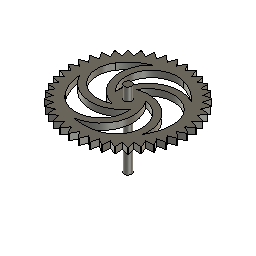
in gear (Autodesk Fusion 360 design; units mm, degrees)
part number: 2026-03-27-23-33-12-431
Autodesk Fusion 360 part; units mm, degrees
sketch "Sketch1" plane through (0, 0, 0) normal (0, 0, 1) x (1, 0, 0)
  circle A0 centre (0, 0) radius 3
  dimension "d1" = 6
  constraint coincident A0.centre origin
  measures "d1" diameter of A0
extrude "Extrude1" add sketch "Sketch1" along normal blind 49.5
sketch "Sketch2" plane through (0, 0, 49.5) normal (0, 0, 1) x (-1, 0, 0)
  circle A0 centre (0, 0) radius 3
  circle A1 centre (0, 0) radius 41
  dimension "d4" = 82
  constraint concentric A0 A1
  measures "d4" diameter of A1
extrude "Extrude2" add sketch "Sketch2" against normal blind 5
sketch "Sketch3" plane through (0, 0, 49.5) normal (0, 0, 1) x (-1, 0, 0)
  circle A0 centre (0, 0) radius 41
  line L0 (-3.4641, -40.8534) -> (0, -46.8534)
  line L1 (0, -46.8534) -> (3.4641, -40.8534)
  line L2 (3.4641, -40.8534) -> (-3.4641, -40.8534)
  point P0 (0, -42.8534)
  dimension "d7" = 2
  constraint horizontal L2
  constraint coincident A0 L1.end
  constraint coincident A0 L0.start
  measures "d7" distance of P0 L2
extrude "Extrude3" add sketch "Sketch3" against normal up to surface (5 mm away) contours A0 L0 L1
fillet "Fillet1" radius 0.5 1 edges at (0, 46.8534, 47)
pattern_circular "C-Pattern1" count 40 over 360 about axis through (0, 0, 1.75) along (0, 0, 1) of "Extrude3", "Fillet1"
sketch "Sketch4" plane through (0, 0, 49.5) normal (0, 0, 1) x (-1, 0, 0)
  arc A0 (-7.6398, -45.468) -> (-6.7845, -45.6035) centre (-7.1731, -45.2889) ccw
  line L0 (-6.7845, -45.6035) -> (-3.2451, -41.2327)
  line L1 (-3.2451, -41.2327) -> (-0.433, -46.1034)
  arc A1 (-0.433, -46.1034) -> (0.433, -46.1034) centre (0, -45.8534) ccw
  line L2 (0.433, -46.1034) -> (3.2451, -41.2327)
  line L3 (3.2451, -41.2327) -> (6.7845, -45.6035)
  arc A2 (6.7845, -45.6035) -> (7.6398, -45.468) centre (7.1731, -45.2889) ccw
  line L4 (7.6398, -45.468) -> (9.6554, -40.2175)
  line L5 (9.6554, -40.2175) -> (13.8349, -43.9807)
  arc A3 (13.8349, -43.9807) -> (14.6586, -43.7131) centre (14.1695, -43.6092) ccw
  line L6 (14.6586, -43.7131) -> (15.8279, -38.2119)
  line L7 (15.8279, -38.2119) -> (20.5447, -41.275)
  arc A4 (20.5447, -41.275) -> (21.3163, -40.8818) centre (20.817, -40.8557) ccw
  line L8 (21.3163, -40.8818) -> (21.6107, -35.2654)
  line L9 (21.6107, -35.2654) -> (26.7486, -37.5529)
  arc A5 (26.7486, -37.5529) -> (27.4492, -37.0439) centre (26.952, -37.0962) ccw
  line L10 (27.4492, -37.0439) -> (26.8613, -31.4506)
  line L11 (26.8613, -31.4506) -> (32.2938, -32.9062)
  arc A6 (32.2938, -32.9062) -> (32.9062, -32.2938) centre (32.4232, -32.4232) ccw
  line L12 (32.9062, -32.2938) -> (31.4506, -26.8613)
  line L13 (31.4506, -26.8613) -> (37.0439, -27.4492)
  arc A7 (37.0439, -27.4492) -> (37.5529, -26.7486) centre (37.0962, -26.952) ccw
  line L14 (37.5529, -26.7486) -> (35.2654, -21.6107)
  line L15 (35.2654, -21.6107) -> (40.8818, -21.3163)
  arc A8 (40.8818, -21.3163) -> (41.275, -20.5447) centre (40.8557, -20.817) ccw
  line L16 (41.275, -20.5447) -> (38.2119, -15.8279)
  line L17 (38.2119, -15.8279) -> (43.7131, -14.6586)
  arc A9 (43.7131, -14.6586) -> (43.9807, -13.8349) centre (43.6092, -14.1695) ccw
  line L18 (43.9807, -13.8349) -> (40.2175, -9.6554)
  line L19 (40.2175, -9.6554) -> (45.468, -7.6398)
  arc A10 (45.468, -7.6398) -> (45.6035, -6.7845) centre (45.2889, -7.1731) ccw
  line L20 (45.6035, -6.7845) -> (41.2327, -3.2451)
  line L21 (41.2327, -3.2451) -> (46.1034, -0.433)
  arc A11 (46.1034, -0.433) -> (46.1034, 0.433) centre (45.8534, 0) ccw
  line L22 (46.1034, 0.433) -> (41.2327, 3.2451)
  line L23 (41.2327, 3.2451) -> (45.6035, 6.7845)
  arc A12 (45.6035, 6.7845) -> (45.468, 7.6398) centre (45.2889, 7.1731) ccw
  line L24 (45.468, 7.6398) -> (40.2175, 9.6554)
  line L25 (40.2175, 9.6554) -> (43.9807, 13.8349)
  arc A13 (43.9807, 13.8349) -> (43.7131, 14.6586) centre (43.6092, 14.1695) ccw
  line L26 (43.7131, 14.6586) -> (38.2119, 15.8279)
  line L27 (38.2119, 15.8279) -> (41.275, 20.5447)
  arc A14 (41.275, 20.5447) -> (40.8818, 21.3163) centre (40.8557, 20.817) ccw
  line L28 (40.8818, 21.3163) -> (35.2654, 21.6107)
  line L29 (35.2654, 21.6107) -> (37.5529, 26.7486)
  arc A15 (37.5529, 26.7486) -> (37.0439, 27.4492) centre (37.0962, 26.952) ccw
  line L30 (37.0439, 27.4492) -> (31.4506, 26.8613)
  line L31 (31.4506, 26.8613) -> (32.9062, 32.2938)
  arc A16 (32.9062, 32.2938) -> (32.2938, 32.9062) centre (32.4232, 32.4232) ccw
  line L32 (32.2938, 32.9062) -> (26.8613, 31.4506)
  line L33 (26.8613, 31.4506) -> (27.4492, 37.0439)
  arc A17 (27.4492, 37.0439) -> (26.7486, 37.5529) centre (26.952, 37.0962) ccw
  line L34 (26.7486, 37.5529) -> (21.6107, 35.2654)
  line L35 (21.6107, 35.2654) -> (21.3163, 40.8818)
  arc A18 (21.3163, 40.8818) -> (20.5447, 41.275) centre (20.817, 40.8557) ccw
  line L36 (20.5447, 41.275) -> (15.8279, 38.2119)
  line L37 (15.8279, 38.2119) -> (14.6586, 43.7131)
  arc A19 (14.6586, 43.7131) -> (13.8349, 43.9807) centre (14.1695, 43.6092) ccw
  line L38 (13.8349, 43.9807) -> (9.6554, 40.2175)
  line L39 (9.6554, 40.2175) -> (7.6398, 45.468)
  arc A20 (7.6398, 45.468) -> (6.7845, 45.6035) centre (7.1731, 45.2889) ccw
  line L40 (6.7845, 45.6035) -> (3.2451, 41.2327)
  line L41 (3.2451, 41.2327) -> (0.433, 46.1034)
  arc A21 (0.433, 46.1034) -> (-0.433, 46.1034) centre (0, 45.8534) ccw
  line L42 (-0.433, 46.1034) -> (-3.2451, 41.2327)
  line L43 (-3.2451, 41.2327) -> (-6.7845, 45.6035)
  arc A22 (-6.7845, 45.6035) -> (-7.6398, 45.468) centre (-7.1731, 45.2889) ccw
  line L44 (-7.6398, 45.468) -> (-9.6554, 40.2175)
  line L45 (-9.6554, 40.2175) -> (-13.8349, 43.9807)
  arc A23 (-13.8349, 43.9807) -> (-14.6586, 43.7131) centre (-14.1695, 43.6092) ccw
  line L46 (-14.6586, 43.7131) -> (-15.8279, 38.2119)
  line L47 (-15.8279, 38.2119) -> (-20.5447, 41.275)
  arc A24 (-20.5447, 41.275) -> (-21.3163, 40.8818) centre (-20.817, 40.8557) ccw
  line L48 (-21.3163, 40.8818) -> (-21.6107, 35.2654)
  line L49 (-21.6107, 35.2654) -> (-26.7486, 37.5529)
  arc A25 (-26.7486, 37.5529) -> (-27.4492, 37.0439) centre (-26.952, 37.0962) ccw
  line L50 (-27.4492, 37.0439) -> (-26.8613, 31.4506)
  line L51 (-26.8613, 31.4506) -> (-32.2938, 32.9062)
  arc A26 (-32.2938, 32.9062) -> (-32.9062, 32.2938) centre (-32.4232, 32.4232) ccw
  line L52 (-32.9062, 32.2938) -> (-31.4506, 26.8613)
  line L53 (-31.4506, 26.8613) -> (-37.0439, 27.4492)
  arc A27 (-37.0439, 27.4492) -> (-37.5529, 26.7486) centre (-37.0962, 26.952) ccw
  line L54 (-37.5529, 26.7486) -> (-35.2654, 21.6107)
  line L55 (-35.2654, 21.6107) -> (-40.8818, 21.3163)
  arc A28 (-40.8818, 21.3163) -> (-41.275, 20.5447) centre (-40.8557, 20.817) ccw
  line L56 (-41.275, 20.5447) -> (-38.2119, 15.8279)
  line L57 (-38.2119, 15.8279) -> (-43.7131, 14.6586)
  arc A29 (-43.7131, 14.6586) -> (-43.9807, 13.8349) centre (-43.6092, 14.1695) ccw
  line L58 (-43.9807, 13.8349) -> (-40.2175, 9.6554)
  line L59 (-40.2175, 9.6554) -> (-45.468, 7.6398)
  arc A30 (-45.468, 7.6398) -> (-45.6035, 6.7845) centre (-45.2889, 7.1731) ccw
  line L60 (-45.6035, 6.7845) -> (-41.2327, 3.2451)
  line L61 (-41.2327, 3.2451) -> (-46.1034, 0.433)
  arc A31 (-46.1034, 0.433) -> (-46.1034, -0.433) centre (-45.8534, 0) ccw
  line L62 (-46.1034, -0.433) -> (-41.2327, -3.2451)
  line L63 (-41.2327, -3.2451) -> (-45.6035, -6.7845)
  arc A32 (-45.6035, -6.7845) -> (-45.468, -7.6398) centre (-45.2889, -7.1731) ccw
  line L64 (-45.468, -7.6398) -> (-40.2175, -9.6554)
  line L65 (-40.2175, -9.6554) -> (-43.9807, -13.8349)
  arc A33 (-43.9807, -13.8349) -> (-43.7131, -14.6586) centre (-43.6092, -14.1695) ccw
  line L66 (-43.7131, -14.6586) -> (-38.2119, -15.8279)
  line L67 (-38.2119, -15.8279) -> (-41.275, -20.5447)
  arc A34 (-41.275, -20.5447) -> (-40.8818, -21.3163) centre (-40.8557, -20.817) ccw
  line L68 (-40.8818, -21.3163) -> (-35.2654, -21.6107)
  line L69 (-35.2654, -21.6107) -> (-37.5529, -26.7486)
  arc A35 (-37.5529, -26.7486) -> (-37.0439, -27.4492) centre (-37.0962, -26.952) ccw
  line L70 (-37.0439, -27.4492) -> (-31.4506, -26.8613)
  line L71 (-31.4506, -26.8613) -> (-32.9062, -32.2938)
  arc A36 (-32.9062, -32.2938) -> (-32.2938, -32.9062) centre (-32.4232, -32.4232) ccw
  line L72 (-32.2938, -32.9062) -> (-26.8613, -31.4506)
  line L73 (-26.8613, -31.4506) -> (-27.4492, -37.0439)
  arc A37 (-27.4492, -37.0439) -> (-26.7486, -37.5529) centre (-26.952, -37.0962) ccw
  line L74 (-26.7486, -37.5529) -> (-21.6107, -35.2654)
  line L75 (-21.6107, -35.2654) -> (-21.3163, -40.8818)
  arc A38 (-21.3163, -40.8818) -> (-20.5447, -41.275) centre (-20.817, -40.8557) ccw
  line L76 (-20.5447, -41.275) -> (-15.8279, -38.2119)
  line L77 (-15.8279, -38.2119) -> (-14.6586, -43.7131)
  arc A39 (-14.6586, -43.7131) -> (-13.8349, -43.9807) centre (-14.1695, -43.6092) ccw
  line L78 (-13.8349, -43.9807) -> (-9.6554, -40.2175)
  line L79 (-9.6554, -40.2175) -> (-7.6398, -45.468)
  circle A40 centre (0, 0) radius 35
  circle A41 centre (0, 0) radius 5
  arc A42 (-34.9762, -1.2899) -> (4.9966, 0.1843) centre (-14.9898, -0.5528) ccw
  arc A43 (-26.6834, -22.6495) -> (10.0084, -0.2575) centre (-14.9898, -0.5528) ccw
  arc A44 (-9.5814, -33.663) -> (1.3688, 4.809) centre (-4.1063, -14.427) ccw
  arc A45 (13.2953, -32.3765) -> (3.3377, 9.439) centre (-4.1063, -14.427) ccw
  arc A46 (29.0546, -19.5149) -> (-4.1507, 2.7878) centre (12.452, -8.3635) ccw
  arc A47 (34.9003, 2.6397) -> (-7.9456, 6.0912) centre (12.452, -8.3635) ccw
  arc A48 (27.5381, 21.6021) -> (-3.934, -3.086) centre (11.8021, 9.258) ccw
  arc A49 (8.2743, 34.0079) -> (-8.2484, -5.6745) centre (11.8021, 9.258) ccw
  arc A50 (-12.0351, 32.8657) -> (1.7193, -4.6951) centre (-5.1579, 14.0853) ccw
  arc A51 (-29.7865, 18.3783) -> (2.8478, -9.5982) centre (-5.1579, 14.0853) ccw
  dimension "d14" = 70
  dimension "d15" = 10
  constraint coincident A40.centre A41.centre
  constraint tangent A40 A42
  constraint tangent A41 A42
  constraint coincident A41 A42.end
  constraint coincident A40 A42.start
  constraint coincident A40 A47.start
  constraint coincident A46 A45.end
  constraint concentric A42 A43
  constraint coincident A44 A43.end
  constraint coincident A42 A51.end
  constraint coincident A50 A49.end
  constraint coincident A48 A47.end
  constraint coincident A40 A49.start
  constraint coincident A40 A51.start
  constraint coincident A40 A43.start
  constraint coincident A40 A45.start
  measures "d14" diameter of A40
  measures "d15" diameter of A41
extrude "Extrude4" cut sketch "Sketch4" against normal blind 5 contours A40 A47 A48 | A40 A45 A46 | A40 A49 A50 | A40 A43 A44 | A40 A42 A51
sketch "Sketch5" plane through (0, 0, 49.5) normal (0, 0, 1) x (-1, 0, 0)
  arc A0 (-29.7865, 18.3783) -> (2.8478, -9.5982) centre (-5.1579, 14.0853) ccw
  arc A1 (-34.9762, -1.2899) -> (2.8478, -9.5982) centre (-14.9898, -0.5528) ccw
  arc A2 (-29.7865, 18.3783) -> (-34.9762, -1.2899) centre (0, 0) ccw
  arc A3 (-9.5814, -33.663) -> (10.0084, -0.2575) centre (-4.1063, -14.427) ccw
  arc A4 (-26.6834, -22.6495) -> (-9.5814, -33.663) centre (0, 0) ccw
  arc A5 (-26.6834, -22.6495) -> (10.0084, -0.2575) centre (-14.9898, -0.5528) ccw
  arc A6 (-12.0351, 32.8657) -> (-8.2484, -5.6745) centre (-5.1579, 14.0853) ccw
  arc A7 (8.2743, 34.0079) -> (-12.0351, 32.8657) centre (0, 0) ccw
  arc A8 (8.2743, 34.0079) -> (-8.2484, -5.6745) centre (11.8021, 9.258) ccw
  arc A9 (29.0546, -19.5149) -> (3.3377, 9.439) centre (12.452, -8.3635) ccw
  arc A10 (13.2953, -32.3765) -> (29.0546, -19.5149) centre (0, 0) ccw
  arc A11 (13.2953, -32.3765) -> (3.3377, 9.439) centre (-4.1063, -14.427) ccw
  arc A12 (27.5381, 21.6021) -> (-7.9456, 6.0912) centre (11.8021, 9.258) ccw
  arc A13 (34.9003, 2.6397) -> (27.5381, 21.6021) centre (0, 0) ccw
  arc A14 (34.9003, 2.6397) -> (-7.9456, 6.0912) centre (12.452, -8.3635) ccw
  arc A15 (-7.6398, -45.468) -> (-6.7845, -45.6035) centre (-7.1731, -45.2889) ccw
  line L0 (-6.7845, -45.6035) -> (-3.2451, -41.2327)
  line L1 (-3.2451, -41.2327) -> (-0.433, -46.1034)
  arc A16 (-0.433, -46.1034) -> (0.433, -46.1034) centre (0, -45.8534) ccw
  line L2 (0.433, -46.1034) -> (3.2451, -41.2327)
  line L3 (3.2451, -41.2327) -> (6.7845, -45.6035)
  arc A17 (6.7845, -45.6035) -> (7.6398, -45.468) centre (7.1731, -45.2889) ccw
  line L4 (7.6398, -45.468) -> (9.6554, -40.2175)
  line L5 (9.6554, -40.2175) -> (13.8349, -43.9807)
  arc A18 (13.8349, -43.9807) -> (14.6586, -43.7131) centre (14.1695, -43.6092) ccw
  line L6 (14.6586, -43.7131) -> (15.8279, -38.2119)
  line L7 (15.8279, -38.2119) -> (20.5447, -41.275)
  arc A19 (20.5447, -41.275) -> (21.3163, -40.8818) centre (20.817, -40.8557) ccw
  line L8 (21.3163, -40.8818) -> (21.6107, -35.2654)
  line L9 (21.6107, -35.2654) -> (26.7486, -37.5529)
  arc A20 (26.7486, -37.5529) -> (27.4492, -37.0439) centre (26.952, -37.0962) ccw
  line L10 (27.4492, -37.0439) -> (26.8613, -31.4506)
  line L11 (26.8613, -31.4506) -> (32.2938, -32.9062)
  arc A21 (32.2938, -32.9062) -> (32.9062, -32.2938) centre (32.4232, -32.4232) ccw
  line L12 (32.9062, -32.2938) -> (31.4506, -26.8613)
  line L13 (31.4506, -26.8613) -> (37.0439, -27.4492)
  arc A22 (37.0439, -27.4492) -> (37.5529, -26.7486) centre (37.0962, -26.952) ccw
  line L14 (37.5529, -26.7486) -> (35.2654, -21.6107)
  line L15 (35.2654, -21.6107) -> (40.8818, -21.3163)
  arc A23 (40.8818, -21.3163) -> (41.275, -20.5447) centre (40.8557, -20.817) ccw
  line L16 (41.275, -20.5447) -> (38.2119, -15.8279)
  line L17 (38.2119, -15.8279) -> (43.7131, -14.6586)
  arc A24 (43.7131, -14.6586) -> (43.9807, -13.8349) centre (43.6092, -14.1695) ccw
  line L18 (43.9807, -13.8349) -> (40.2175, -9.6554)
  line L19 (40.2175, -9.6554) -> (45.468, -7.6398)
  arc A25 (45.468, -7.6398) -> (45.6035, -6.7845) centre (45.2889, -7.1731) ccw
  line L20 (45.6035, -6.7845) -> (41.2327, -3.2451)
  line L21 (41.2327, -3.2451) -> (46.1034, -0.433)
  arc A26 (46.1034, -0.433) -> (46.1034, 0.433) centre (45.8534, 0) ccw
  line L22 (46.1034, 0.433) -> (41.2327, 3.2451)
  line L23 (41.2327, 3.2451) -> (45.6035, 6.7845)
  arc A27 (45.6035, 6.7845) -> (45.468, 7.6398) centre (45.2889, 7.1731) ccw
  line L24 (45.468, 7.6398) -> (40.2175, 9.6554)
  line L25 (40.2175, 9.6554) -> (43.9807, 13.8349)
  arc A28 (43.9807, 13.8349) -> (43.7131, 14.6586) centre (43.6092, 14.1695) ccw
  line L26 (43.7131, 14.6586) -> (38.2119, 15.8279)
  line L27 (38.2119, 15.8279) -> (41.275, 20.5447)
  arc A29 (41.275, 20.5447) -> (40.8818, 21.3163) centre (40.8557, 20.817) ccw
  line L28 (40.8818, 21.3163) -> (35.2654, 21.6107)
  line L29 (35.2654, 21.6107) -> (37.5529, 26.7486)
  arc A30 (37.5529, 26.7486) -> (37.0439, 27.4492) centre (37.0962, 26.952) ccw
  line L30 (37.0439, 27.4492) -> (31.4506, 26.8613)
  line L31 (31.4506, 26.8613) -> (32.9062, 32.2938)
  arc A31 (32.9062, 32.2938) -> (32.2938, 32.9062) centre (32.4232, 32.4232) ccw
  line L32 (32.2938, 32.9062) -> (26.8613, 31.4506)
  line L33 (26.8613, 31.4506) -> (27.4492, 37.0439)
  arc A32 (27.4492, 37.0439) -> (26.7486, 37.5529) centre (26.952, 37.0962) ccw
  line L34 (26.7486, 37.5529) -> (21.6107, 35.2654)
  line L35 (21.6107, 35.2654) -> (21.3163, 40.8818)
  arc A33 (21.3163, 40.8818) -> (20.5447, 41.275) centre (20.817, 40.8557) ccw
  line L36 (20.5447, 41.275) -> (15.8279, 38.2119)
  line L37 (15.8279, 38.2119) -> (14.6586, 43.7131)
  arc A34 (14.6586, 43.7131) -> (13.8349, 43.9807) centre (14.1695, 43.6092) ccw
  line L38 (13.8349, 43.9807) -> (9.6554, 40.2175)
  line L39 (9.6554, 40.2175) -> (7.6398, 45.468)
  arc A35 (7.6398, 45.468) -> (6.7845, 45.6035) centre (7.1731, 45.2889) ccw
  line L40 (6.7845, 45.6035) -> (3.2451, 41.2327)
  line L41 (3.2451, 41.2327) -> (0.433, 46.1034)
  arc A36 (0.433, 46.1034) -> (-0.433, 46.1034) centre (0, 45.8534) ccw
  line L42 (-0.433, 46.1034) -> (-3.2451, 41.2327)
  line L43 (-3.2451, 41.2327) -> (-6.7845, 45.6035)
  arc A37 (-6.7845, 45.6035) -> (-7.6398, 45.468) centre (-7.1731, 45.2889) ccw
  line L44 (-7.6398, 45.468) -> (-9.6554, 40.2175)
  line L45 (-9.6554, 40.2175) -> (-13.8349, 43.9807)
  arc A38 (-13.8349, 43.9807) -> (-14.6586, 43.7131) centre (-14.1695, 43.6092) ccw
  line L46 (-14.6586, 43.7131) -> (-15.8279, 38.2119)
  line L47 (-15.8279, 38.2119) -> (-20.5447, 41.275)
  arc A39 (-20.5447, 41.275) -> (-21.3163, 40.8818) centre (-20.817, 40.8557) ccw
  line L48 (-21.3163, 40.8818) -> (-21.6107, 35.2654)
  line L49 (-21.6107, 35.2654) -> (-26.7486, 37.5529)
  arc A40 (-26.7486, 37.5529) -> (-27.4492, 37.0439) centre (-26.952, 37.0962) ccw
  line L50 (-27.4492, 37.0439) -> (-26.8613, 31.4506)
  line L51 (-26.8613, 31.4506) -> (-32.2938, 32.9062)
  arc A41 (-32.2938, 32.9062) -> (-32.9062, 32.2938) centre (-32.4232, 32.4232) ccw
  line L52 (-32.9062, 32.2938) -> (-31.4506, 26.8613)
  line L53 (-31.4506, 26.8613) -> (-37.0439, 27.4492)
  arc A42 (-37.0439, 27.4492) -> (-37.5529, 26.7486) centre (-37.0962, 26.952) ccw
  line L54 (-37.5529, 26.7486) -> (-35.2654, 21.6107)
  line L55 (-35.2654, 21.6107) -> (-40.8818, 21.3163)
  arc A43 (-40.8818, 21.3163) -> (-41.275, 20.5447) centre (-40.8557, 20.817) ccw
  line L56 (-41.275, 20.5447) -> (-38.2119, 15.8279)
  line L57 (-38.2119, 15.8279) -> (-43.7131, 14.6586)
  arc A44 (-43.7131, 14.6586) -> (-43.9807, 13.8349) centre (-43.6092, 14.1695) ccw
  line L58 (-43.9807, 13.8349) -> (-40.2175, 9.6554)
  line L59 (-40.2175, 9.6554) -> (-45.468, 7.6398)
  arc A45 (-45.468, 7.6398) -> (-45.6035, 6.7845) centre (-45.2889, 7.1731) ccw
  line L60 (-45.6035, 6.7845) -> (-41.2327, 3.2451)
  line L61 (-41.2327, 3.2451) -> (-46.1034, 0.433)
  arc A46 (-46.1034, 0.433) -> (-46.1034, -0.433) centre (-45.8534, 0) ccw
  line L62 (-46.1034, -0.433) -> (-41.2327, -3.2451)
  line L63 (-41.2327, -3.2451) -> (-45.6035, -6.7845)
  arc A47 (-45.6035, -6.7845) -> (-45.468, -7.6398) centre (-45.2889, -7.1731) ccw
  line L64 (-45.468, -7.6398) -> (-40.2175, -9.6554)
  line L65 (-40.2175, -9.6554) -> (-43.9807, -13.8349)
  arc A48 (-43.9807, -13.8349) -> (-43.7131, -14.6586) centre (-43.6092, -14.1695) ccw
  line L66 (-43.7131, -14.6586) -> (-38.2119, -15.8279)
  line L67 (-38.2119, -15.8279) -> (-41.275, -20.5447)
  arc A49 (-41.275, -20.5447) -> (-40.8818, -21.3163) centre (-40.8557, -20.817) ccw
  line L68 (-40.8818, -21.3163) -> (-35.2654, -21.6107)
  line L69 (-35.2654, -21.6107) -> (-37.5529, -26.7486)
  arc A50 (-37.5529, -26.7486) -> (-37.0439, -27.4492) centre (-37.0962, -26.952) ccw
  line L70 (-37.0439, -27.4492) -> (-31.4506, -26.8613)
  line L71 (-31.4506, -26.8613) -> (-32.9062, -32.2938)
  arc A51 (-32.9062, -32.2938) -> (-32.2938, -32.9062) centre (-32.4232, -32.4232) ccw
  line L72 (-32.2938, -32.9062) -> (-26.8613, -31.4506)
  line L73 (-26.8613, -31.4506) -> (-27.4492, -37.0439)
  arc A52 (-27.4492, -37.0439) -> (-26.7486, -37.5529) centre (-26.952, -37.0962) ccw
  line L74 (-26.7486, -37.5529) -> (-21.6107, -35.2654)
  line L75 (-21.6107, -35.2654) -> (-21.3163, -40.8818)
  arc A53 (-21.3163, -40.8818) -> (-20.5447, -41.275) centre (-20.817, -40.8557) ccw
  line L76 (-20.5447, -41.275) -> (-15.8279, -38.2119)
  line L77 (-15.8279, -38.2119) -> (-14.6586, -43.7131)
  arc A54 (-14.6586, -43.7131) -> (-13.8349, -43.9807) centre (-14.1695, -43.6092) ccw
  line L78 (-13.8349, -43.9807) -> (-9.6554, -40.2175)
  line L79 (-9.6554, -40.2175) -> (-7.6398, -45.468)
  circle A55 centre (0, 0) radius 3
  constraint coincident A2.centre A4.centre
extrude "Extrude5" add sketch "Sketch5" along normal blind 10 contours A55
equation "d4 = ( 41 * 2 ) * 1 mm"
